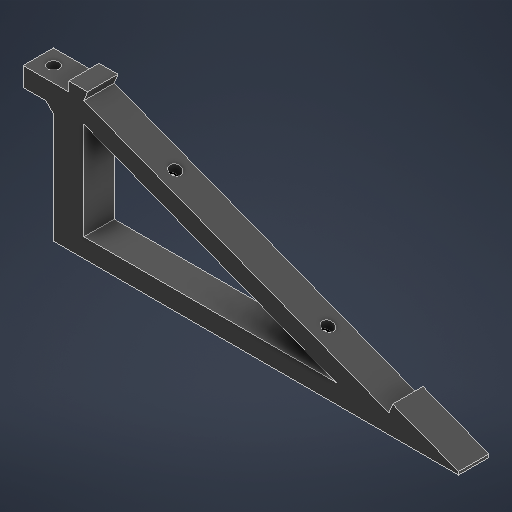
# Autodesk Inventor part: Slope_Stand
Saved by Autodesk Inventor 2027.1 (Build 311270010, 270A)
## iProperties
Created: 2026-10-10
Part Number: Slope_Stand
Material: 一般
Document SubType Name: Modeling
Designer: Takuya Kamada
Density: 1 g/cm^3
Appearance: 一般
Author: Takuya Kamada
Autodesk Inventor part; units mm, degrees
ref_plane "YZ Plane" through (0, 0, 0) normal (1, 0, 0) x (0, 1, 0)
ref_plane "XZ Plane" through (0, 0, 0) normal (0, 1, 0) x (-1, 0, 0)
ref_plane "XY Plane" through (0, 0, 0) normal (0, 0, 1) x (1, 0, 0)
sketch "スケッチ1" plane through (0, 0, 0) normal (0, 0, 1) x (1, 0, 0)
  line L0 (88, 0) -> (100, 0) projected
  line L1 (100, 0) -> (100, 2.5) projected
  line L2 (88, 2.5) -> (100, 2.5) projected
  line L3 (100, 0) -> (87.3841, 0)
  line L4 (-83.2436, -36) -> (-8.2436, -36) projected
  line L5 (104.9661, 2.5) -> (104, 0)
  line L6 (104, 0) -> (184.216, -31)
  line L7 (184.216, -31) -> (185.1821, -28.5)
  line L8 (185.1821, -28.5) -> (104.9661, 2.5)
  line L9 (96, 0) -> (104, 0)
  line L10 (104, 0) -> (104, -36)
  line L11 (104, -36) -> (96, -36)
  line L12 (96, -36) -> (96, 0)
  line L13 (104, -36) -> (184.216, -36)
  line L14 (184.216, -36) -> (184.216, -31)
  line L15 (184.216, -31) -> (104, -31)
  line L16 (104, -31) -> (104, -36)
  line L17 (100, 2.5) -> (104.9661, 2.5)
  line L18 (185.1821, -28.5) -> (204.5892, -36)
  line L19 (204.5892, -36) -> (184.216, -36)
  line L20 (104, 0) -> (184.216, -31)
  line L21 (184.216, -31) -> (182.4136, -35.6638)
  line L22 (182.4136, -35.6638) -> (102.1976, -4.6638)
  line L23 (102.1976, -4.6638) -> (104, 0)
  line L24 (202.5191, -35.2) -> (202.5191, -36)
  line L25 (88, 2.5) -> (88, 0) projected
  point P0 (104, -5.3604)
  point P1 (170.3454, -31)
  dimension "d2" = 2.5
  dimension "d3" = 8
  dimension "d5" = 5
  dimension "d6" = 5
  dimension "d7" = 0.8
  constraints: 42 end point, 8 parallel, 5 perpendicular, 4 horizontal, 3 point on line, 2 coincident, 2 collinear, 2 horizontal alignment, 1 midpoint
  measures "d2" vertical distance of L5.start L5.end
  measures "d3" distance of L9.start L9.end
  measures "d5" distance between parallel lines of L13 L15
  measures "d6" distance of L6.end L21.end
  measures "d7" distance of L24.start L24.end
extrude "押し出し1" add sketch "スケッチ1" against normal blind 8 contours L0 L9 L23 L22 L10 L11 L12 | L1 L17 L5 L9 | L6 L15 L22 L10 | L10 L22 L23 | L10 L15 L22 L21 L14 L13 | L7 L18 L24 L19 L14 | L21 L22 L15
sketch "スケッチ2" plane through (184.216, -31, 0) normal (0.3604749, 0.9327689, 0) x (0.9327689, -0.3604749, 0)
  line L0 (-85.9977, 0) -> (-85.9977, 8) projected
  line L1 (-85.9977, 8) -> (0, 8) projected
  line L2 (0, 0) -> (0, 8) projected
  line L3 (0, 0) -> (-85.9977, 0) projected
  line L4 (0, 8) -> (-42.9988, 8)
  line L5 (-42.9988, 8) -> (-42.9988, 0)
  line L6 (-42.9988, 0) -> (0, 0)
  line L7 (0, 0) -> (0, 8)
  line L8 (-42.9988, 0) -> (-85.9977, 0)
  line L9 (-85.9977, 0) -> (-85.9977, 8)
  line L10 (-85.9977, 8) -> (-42.9988, 8)
  line L11 (-42.9988, 8) -> (-42.9988, 0)
  circle A0 centre (-64.4983, 4) radius 1.5
  circle A1 centre (-21.4994, 4) radius 1.5
  point P0 (-183.0056, 0)
  dimension "d10" = 3
  dimension "d11" = 3
  constraints: 16 end point, 4 parallel, 2 centre point, 2 horizontal, 2 perpendicular, 1 midpoint
  measures "d10" diameter of A0
  measures "d11" diameter of A1
extrude "押し出し2" cut sketch "スケッチ2" against normal up to surface (5 mm away) contours A0 | A1
sketch "スケッチ3" plane through (104, -5.3604, -8) normal (-0.3604749, -0.9327689, 0) x (0.9327689, -0.3604749, 0)
  circle A0 centre (62.566, 4) radius 1.5 projected
  circle A1 centre (19.5671, 4) radius 1.5 projected
  line L0 (84.0654, 8) -> (-1.9323, 8) projected
  line L1 (84.0654, 8) -> (84.0654, 0) projected
  line L2 (-1.9323, 0) -> (84.0654, 0) projected
  line L3 (-1.9323, 8) -> (-1.9323, 0) projected
  line L4 (21.2126, 6.85) -> (22.858, 4)
  line L5 (22.858, 4) -> (21.2126, 1.15)
  line L6 (21.2126, 1.15) -> (17.9217, 1.15)
  line L7 (17.9217, 1.15) -> (16.2762, 4)
  line L8 (16.2762, 4) -> (17.9217, 6.85)
  line L9 (17.9217, 6.85) -> (21.2126, 6.85)
  line L10 (64.2114, 6.85) -> (65.8569, 4)
  line L11 (65.8569, 4) -> (64.2114, 1.15)
  line L12 (64.2114, 1.15) -> (60.9205, 1.15)
  line L13 (60.9205, 1.15) -> (59.2751, 4)
  line L14 (59.2751, 4) -> (60.9205, 6.85)
  line L15 (60.9205, 6.85) -> (64.2114, 6.85)
  point P0 (-98.9403, 8)
  point P1 (62.566, 4)
  point P2 (62.566, 6.85)
  point P3 (19.5671, 1.15)
  point P4 (19.5671, 6.85)
  dimension "d14" = 5.7
  dimension "d15" = 5.7
  constraints: 24 end point, 3 midpoint, 2 coincident, 1 parallel, 1 point on line, 26 other
  measures "d14" distance of point (19.567, 1.15) point (19.567, 6.85)
  measures "d15" distance from line of L12 point (62.566, 6.85)
extrude "押し出し3" cut sketch "スケッチ3" against normal blind 2.4 contours A0 | A1 | L4 L5 L6 L7 L8 L9 | L10 L11 L12 L13 L14 L15
sketch "スケッチ5" plane through (96, 0, 0) normal (0, 1, 0) x (1, 0, 0)
  line L0 (0, 0) -> (0, 8) projected
  line L1 (0, 8) -> (-8, 8)
  line L2 (-8, 8) -> (-8, 0)
  line L3 (-8, 0) -> (0, 0)
  line L4 (0, 0) -> (0, 8)
  point P0 (-96, 0)
  dimension "d18" = 8
  constraints: 8 end point, 2 parallel, 1 horizontal, 1 perpendicular
  measures "d18" distance of L3.end L2.end
extrude "押し出し4" add sketch "スケッチ5" against normal blind 5
sketch "スケッチ6" plane through (96, -5, 0) normal (0, -1, 0) x (1, 0, 0)
  line L0 (0, 0) -> (0, -8) projected
  line L1 (0, 0) -> (-8, 0) projected
  line L2 (-8, 0) -> (-8, -8) projected
  line L3 (-8, -8) -> (0, -8) projected
  circle A0 centre (-4, -4) radius 1.5
  line L4 (-5.6454, -6.85) -> (-7.2909, -4)
  line L5 (-7.2909, -4) -> (-5.6454, -1.15)
  line L6 (-5.6454, -1.15) -> (-2.3546, -1.15)
  line L7 (-2.3546, -1.15) -> (-0.7091, -4)
  line L8 (-0.7091, -4) -> (-2.3546, -6.85)
  line L9 (-2.3546, -6.85) -> (-5.6454, -6.85)
  point P0 (-96, 0)
  dimension "d21" = 3
  dimension "d22" = 5.7
  constraints: 12 end point, 1 centre point, 1 coincident, 13 other
  measures "d21" diameter of A0
  measures "d22" distance between parallel lines of L9 L6
extrude "押し出し5" cut sketch "スケッチ6" against normal blind 2.4 contours A0 | L4 L5 L6 L7 L8 L9
sketch "スケッチ7" plane through (96, -2.6, 0) normal (0, -1, 0) x (1, 0, 0)
  line L0 (-0.7091, -4) -> (-2.3546, -6.85) projected
  line L1 (-2.3546, -1.15) -> (-0.7091, -4) projected
  line L2 (-5.6454, -1.15) -> (-2.3546, -1.15) projected
  line L3 (-7.2909, -4) -> (-5.6454, -1.15) projected
  line L4 (-5.6454, -6.85) -> (-7.2909, -4) projected
  line L5 (-2.3546, -6.85) -> (-5.6454, -6.85) projected
  circle A0 centre (-4, -4) radius 1.5
  point P0 (-96, 0)
  dimension "d25" = 3
  constraints: 1 centre point
  measures "d25" diameter of A0
extrude "押し出し6" cut sketch "スケッチ7" against normal up to surface (2.6 mm away) contours A0
chamfer "面取り1" distance 2 angle 45 1 edges at (96, -5, -4)
equation "\"d15\" = d14"
